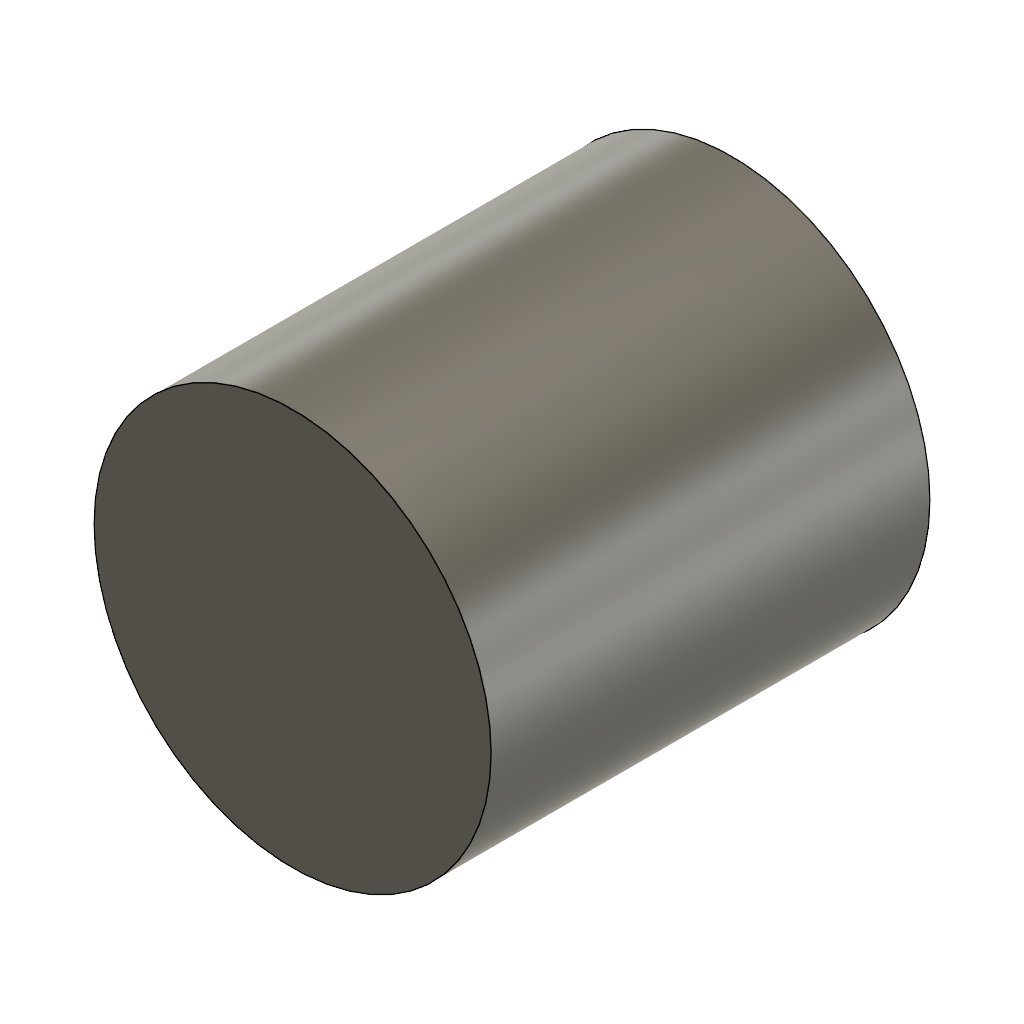
holdout_b (Autodesk Fusion 360 design; units mm, degrees)
part number: 2026-11-27-17-29-35-755
Autodesk Fusion 360 part; units mm, degrees
sketch "CircularProfile" plane through (0, 0, 0) normal (0, 0, 1) x (1, 0, 0)
  circle A0 centre (-9, -17) radius 19
extrude "OffsetTwoSides" add sketch "CircularProfile" along normal blind 31 and the other way blind 11 from surface at 19
